Autodesk Fusion 360 part; units mm, degrees
(part 2 of 2)
ref_plane "WorkPlane88" through (0, 0, 10.6) normal (0, 0, 1) x (1, 0, 0) in component "Handheld Body"
sketch "Sketch88" plane through (0, 0, 10.6) normal (0, 0, 1) x (1, 0, 0) in component "Handheld Body"
  line L0 (86, 2.6) -> (146.8, 2.6)
  line L1 (146.8, 2.6) -> (146.8, 145.4)
  line L2 (146.8, 145.4) -> (86, 145.4)
  line L3 (86, 145.4) -> (86, 2.6)
extrude "Extrude88" add sketch "Sketch88" along normal blind 2 bodies 7 in component "Handheld Body"
ref_plane "WorkPlane89" through (0, 0, 10.6) normal (0, 0, 1) x (1, 0, 0) in component "Handheld Body"
sketch "Sketch89" plane through (0, 0, 10.6) normal (0, 0, 1) x (1, 0, 0) in component "Handheld Body"
  line L0 (144.8, 2.6) -> (146.8, 2.6)
  line L1 (146.8, 2.6) -> (146.8, 145.4)
  line L2 (146.8, 145.4) -> (144.8, 145.4)
  line L3 (144.8, 145.4) -> (144.8, 2.6)
extrude "Extrude89" add sketch "Sketch89" along normal blind 37.4 bodies 7 in component "Handheld Body"
ref_plane "WorkPlane90" through (0, 0, 12.6) normal (0, 0, 1) x (1, 0, 0) in component "Handheld Body"
sketch "Sketch90" plane through (0, 0, 12.6) normal (0, 0, 1) x (1, 0, 0) in component "Handheld Body"
  line L0 (88, 2.6) -> (144.8, 2.6)
  line L1 (144.8, 2.6) -> (144.8, 5.6)
  line L2 (144.8, 5.6) -> (88, 5.6)
  line L3 (88, 5.6) -> (88, 2.6)
extrude "Extrude90" add sketch "Sketch90" along normal blind 35.4 bodies 7 in component "Handheld Body"
ref_plane "WorkPlane91" through (0, 0, 46.4) normal (0, 0, 1) x (1, 0, 0) in component "Handheld Body"
sketch "Sketch91" plane through (0, 0, 46.4) normal (0, 0, 1) x (1, 0, 0) in component "Handheld Body"
  line L0 (88, 2.6) -> (144.8, 2.6)
  line L1 (144.8, 2.6) -> (144.8, 145.4)
  line L2 (144.8, 145.4) -> (88, 145.4)
  line L3 (88, 145.4) -> (88, 2.6)
extrude "Extrude91" add sketch "Sketch91" along normal blind 1.6 bodies 7 in component "Handheld Body"
ref_plane "WorkPlane92" through (0, 0, 46) normal (0, 0, 1) x (1, 0, 0) in component "Handheld Body"
sketch "Sketch92" plane through (0, 0, 46) normal (0, 0, 1) x (1, 0, 0) in component "Handheld Body"
  line L0 (91, 75) -> (141.8, 75)
  line L1 (141.8, 75) -> (141.8, 133)
  line L2 (141.8, 133) -> (91, 133)
  line L3 (91, 133) -> (91, 75)
extrude "Extrude92" cut sketch "Sketch92" along normal blind 2.5 bodies 7 in component "Handheld Body"
ref_plane "WorkPlane93" through (0, 0, 10.1) normal (0, 0, 1) x (1, 0, 0) in component "Handheld Body"
sketch "Sketch93" plane through (0, 0, 10.1) normal (0, 0, 1) x (1, 0, 0) in component "Handheld Body"
  line L0 (92.4, 120.4) -> (93.4, 120.4)
  line L1 (93.4, 120.4) -> (93.4, 145.9)
  line L2 (93.4, 145.9) -> (92.4, 145.9)
  line L3 (92.4, 145.9) -> (92.4, 120.4)
extrude "Extrude93" cut sketch "Sketch93" along normal blind 3 bodies 7 in component "Handheld Body"
ref_plane "WorkPlane94" through (0, 0, 10.1) normal (0, 0, 1) x (1, 0, 0) in component "Handheld Body"
sketch "Sketch94" plane through (0, 0, 10.1) normal (0, 0, 1) x (1, 0, 0) in component "Handheld Body"
  line L0 (99.4, 120.4) -> (100.4, 120.4)
  line L1 (100.4, 120.4) -> (100.4, 145.9)
  line L2 (100.4, 145.9) -> (99.4, 145.9)
  line L3 (99.4, 145.9) -> (99.4, 120.4)
extrude "Extrude94" cut sketch "Sketch94" along normal blind 3 bodies 7 in component "Handheld Body"
ref_plane "WorkPlane95" through (0, 0, 12.59) normal (0, 0, 1) x (1, 0, 0) in component "Handheld Body"
sketch "Sketch95" plane through (0, 0, 12.59) normal (0, 0, 1) x (1, 0, 0) in component "Handheld Body"
  line L0 (93.4, 141.6) -> (99.4, 141.6)
  line L1 (99.4, 141.6) -> (99.4, 143.6)
  line L2 (99.4, 143.6) -> (93.4, 143.6)
  line L3 (93.4, 143.6) -> (93.4, 141.6)
extrude "Extrude95" add sketch "Sketch95" along normal blind 1.51 bodies 7 in component "Handheld Body"
ref_plane "WorkPlane96" through (0, 0, 10.1) normal (0, 0, 1) x (1, 0, 0) in component "Handheld Body"
sketch "Sketch96" plane through (0, 0, 10.1) normal (0, 0, 1) x (1, 0, 0) in component "Handheld Body"
  line L0 (132.4, 120.4) -> (133.4, 120.4)
  line L1 (133.4, 120.4) -> (133.4, 145.9)
  line L2 (133.4, 145.9) -> (132.4, 145.9)
  line L3 (132.4, 145.9) -> (132.4, 120.4)
extrude "Extrude96" cut sketch "Sketch96" along normal blind 3 bodies 7 in component "Handheld Body"
ref_plane "WorkPlane97" through (0, 0, 10.1) normal (0, 0, 1) x (1, 0, 0) in component "Handheld Body"
sketch "Sketch97" plane through (0, 0, 10.1) normal (0, 0, 1) x (1, 0, 0) in component "Handheld Body"
  line L0 (139.4, 120.4) -> (140.4, 120.4)
  line L1 (140.4, 120.4) -> (140.4, 145.9)
  line L2 (140.4, 145.9) -> (139.4, 145.9)
  line L3 (139.4, 145.9) -> (139.4, 120.4)
extrude "Extrude97" cut sketch "Sketch97" along normal blind 3 bodies 7 in component "Handheld Body"
ref_plane "WorkPlane98" through (0, 0, 12.59) normal (0, 0, 1) x (1, 0, 0) in component "Handheld Body"
sketch "Sketch98" plane through (0, 0, 12.59) normal (0, 0, 1) x (1, 0, 0) in component "Handheld Body"
  line L0 (133.4, 141.6) -> (139.4, 141.6)
  line L1 (139.4, 141.6) -> (139.4, 143.6)
  line L2 (139.4, 143.6) -> (133.4, 143.6)
  line L3 (133.4, 143.6) -> (133.4, 141.6)
extrude "Extrude98" add sketch "Sketch98" along normal blind 1.51 bodies 7 in component "Handheld Body"
ref_plane "WorkPlane99" through (0, 0, 3) normal (0, 0, 1) x (1, 0, 0) in component "Handheld Body"
sketch "Sketch99" plane through (0, 0, 3) normal (0, 0, 1) x (1, 0, 0) in component "Handheld Body"
  line L0 (85.5, 17) -> (88.5, 17)
  line L1 (88.5, 17) -> (88.5, 37)
  line L2 (88.5, 37) -> (85.5, 37)
  line L3 (85.5, 37) -> (85.5, 17)
extrude "Extrude99" cut sketch "Sketch99" along normal blind 12 bodies 7 in component "Handheld Body"
ref_plane "WorkPlane100" through (0, 0, 13) normal (0, 0, 1) x (1, 0, 0) in component "Handheld Body"
sketch "Sketch100" plane through (0, 0, 13) normal (0, 0, 1) x (1, 0, 0) in component "Handheld Body"
  line L0 (85.5, 86) -> (88.5, 86)
  line L1 (88.5, 86) -> (88.5, 122)
  line L2 (88.5, 122) -> (85.5, 122)
  line L3 (85.5, 122) -> (85.5, 86)
extrude "Extrude100" cut sketch "Sketch100" along normal blind 18 bodies 7 in component "Handheld Body"
component "Sensor Head" placed x (1, 0, 0) y (0, 1, 0) z (0, 0, 1) at (0, 0, 0)
component "Handheld Body" placed x (1, 0, 0) y (0, 1, 0) z (0, 0, 1) at (40, -70, 0)
named bodies: "Sensor head", "Head lid", "IMU cradle", "Back shell", "Front lid", "Screen tray", "Bank holder"
